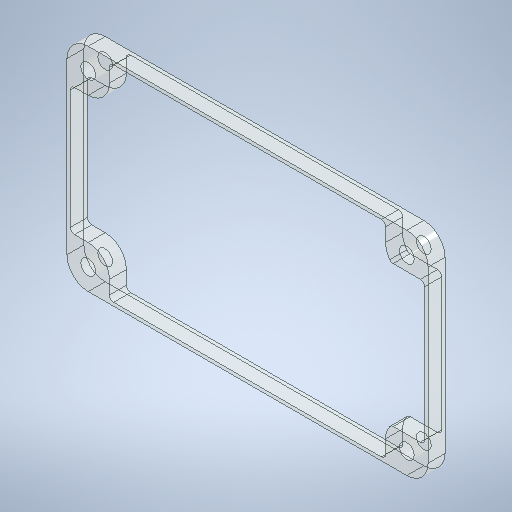
# Autodesk Inventor part: 3D_clear
Saved by Autodesk Inventor 2025.3 (Build 293356030, 356C)
## iProperties
Created: 2026-02-13
Part Number: 3D_clear
Material: 一般
Document SubType Name: Modeling
Designer: ibuki_ono
Density: 1 g/cm^3
Appearance: クリア
Author: ibuki_ono
## iProperties of the stored document 3D_clear_3D プリント.ipt
Created: 2026-02-13
Part Number: 3D_clear_3D プリント
Material: 一般
Document SubType Name: Modeling
Designer: ibuki_ono
Density: 1 g/cm^3
Appearance: 既定
Author: ibuki_ono
Autodesk Inventor part; units mm, degrees
ref_plane "YZ Plane" through (0, 0, 0) normal (1, 0, 0) x (0, 1, 0)
ref_plane "XZ Plane" through (0, 0, 0) normal (0, 1, 0) x (-1, 0, 0)
ref_plane "XY Plane" through (0, 0, 0) normal (0, 0, 1) x (1, 0, 0)
sketch "スケッチ1" plane through (0, 0, 0) normal (0, 0, 1) x (1, 0, 0)
  line L0 (-42.5, -25) -> (42.5, -25)
  line L1 (42.5, -25) -> (42.5, 25)
  line L2 (42.5, 25) -> (-42.5, 25)
  line L3 (-42.5, 25) -> (-42.5, -25)
  line L4 (-42.5, -25) -> (42.5, 25) construction
  line L5 (42.5, -25) -> (-42.5, 25) construction
  line L6 (-41.7, 24.2) -> (41.7, 24.2)
  line L7 (41.7, 24.2) -> (41.7, -24.2)
  line L8 (41.7, -24.2) -> (-41.7, -24.2)
  line L9 (-41.7, -24.2) -> (-41.7, 24.2)
  circle A0 centre (-37.5, 20) radius 5
  circle A1 centre (37.5, 20) radius 5
  circle A2 centre (37.5, -20) radius 5
  circle A3 centre (-37.5, -20) radius 5
  line L10 (-37.5, 15) -> (-41.7, 15)
  line L11 (-32.5, 20) -> (-32.5, 24.2)
  line L12 (32.5, 20) -> (32.5, 24.2)
  line L13 (37.5, 15) -> (41.7, 15)
  line L14 (37.5, -15) -> (41.7, -15)
  line L15 (32.5, -20) -> (32.5, -24.2)
  line L16 (-32.5, -20) -> (-32.5, -24.2)
  line L17 (-37.5, -15) -> (-41.7, -15)
  point P0 (0, 0)
  dimension "d0" = 85
  dimension "d1" = 50
  dimension "d2" = 0.8
  dimension "d3" = 10
  dimension "d4" = 10
  dimension "d5" = 10
  dimension "d6" = 10
  constraints: 36 end point, 16 point on line, 12 tangent, 8 point on circle, 6 perpendicular, 4 centre point, 4 parallel, 2 midpoint, 1 horizontal, 3 other
  measures "d0" distance of L2.end L1.end
  measures "d1" distance of L1.end L0.end
  measures "d2" distance between parallel lines of L2 L6
  measures "d3" diameter of A1
  measures "d4" diameter of A2
  measures "d5" diameter of A3
  measures "d6" diameter of A0
extrude "押し出し1" add sketch "スケッチ1" along normal mid plane 4 contours L3 A3 L9 L8 L0 | A3 L8 A2 L0 | A3 L8 | L3 A0 L9 A3 | A3 L9 | A2 L8 L7 L1 L0 | A2 L8 | A3 L9 L8 | L8 L9 A3 | A3 L16 L8 | L3 L2 A0 L6 L9 | A0 L9 | L9 L17 A3 | A2 L7 L8 | L8 L15 A2 | A2 L7 L8 | A0 L6 L9 | L9 L6 A0 | A0 L10 L9 | A2 L7 A1 L1 | A2 L7 | L2 A1 L6 A0 | A0 L6 | A1 L7 L6 L2 L1 | A1 L7 | A2 L14 L7 | A1 L6 | L6 L11 A0 | A1 L6 L7 | L7 A1 L6 | L7 L13 A1 | A1 L12 L6
sketch "スケッチ2" plane through (0, 0, 2) normal (0, 0, 1) x (1, 0, 0)
  arc A0 (-37.5, 15) -> (-32.5, 20) centre (-37.5, 20) ccw projected
  arc A1 (32.5, 20) -> (37.5, 15) centre (37.5, 20) ccw projected
  arc A2 (37.5, -15) -> (32.5, -20) centre (37.5, -20) ccw projected
  arc A3 (-32.5, -20) -> (-37.5, -15) centre (-37.5, -20) ccw projected
  point P0 (0, 0)
  constraints: 4 coincident
hole "穴1" at (-37.5, 20, 2) at (37.5, 20, 2) at (37.5, -20, 2) at (-37.5, -20, 2) direction (0, 0, -1) diameter 3.5 end through all
fillet "フィレット1" radius 5 4 edges at (-42.5, -25, 0) (-42.5, 25, 0) (42.5, -25, 0) (42.5, 25, 0)
sketch "スケッチ3" plane through (0, 0, 2) normal (0, 0, 1) x (1, 0, 0)
  line L0 (41.7, -15) -> (37.5, -15) projected
  line L1 (37.5, 15) -> (41.7, 15) projected
  line L2 (32.5, 24.2) -> (32.5, 20) projected
  arc A0 (37.5, -15) -> (32.5, -20) centre (37.5, -20) ccw projected
  arc A1 (32.5, 20) -> (37.5, 15) centre (37.5, 20) ccw projected
  line L3 (41.7, 15) -> (33.8339, 15)
  line L4 (33.8339, 15) -> (33.8339, 16.6)
  line L5 (33.8339, 16.6) -> (41.7, 16.6)
  line L6 (41.7, 16.6) -> (41.7, 15)
  line L7 (41.7, -15) -> (33.8339, -15)
  line L8 (33.8339, -15) -> (33.8339, -16.6)
  line L9 (33.8339, -16.6) -> (41.7, -16.6)
  line L10 (41.7, -16.6) -> (41.7, -15)
  point P0 (0, 0)
  dimension "d18" = 1.6
  dimension "d19" = 1.6
  constraints: 16 end point, 4 parallel, 2 horizontal, 2 perpendicular, 2 point on circle
  measures "d18" distance of L3.end L4.end
  measures "d19" distance of L8.end L7.end
extrude "押し出し2" cut sketch "スケッチ3" against normal through all contours L10 L9 A0 L0 | A1 L5 L6 L1
fillet "フィレット2" radius 1 10 edges at (32.5, 24.2, 0) (32.5, -24.2, 0) (-32.5, -24.2, 0) (-41.7, -15, 0) (-41.7, 15, 0) (-32.5, 24.2, 0) (41.7, -16.6, 0) (33.8339, -16.6, 0) (41.7, 16.6, 0) (33.8339, 16.6, 0)
equation "\"d4\" = d3"
equation "\"d5\" = d3"
equation "\"d6\" = d3"
equation "\"d19\" = d18"
